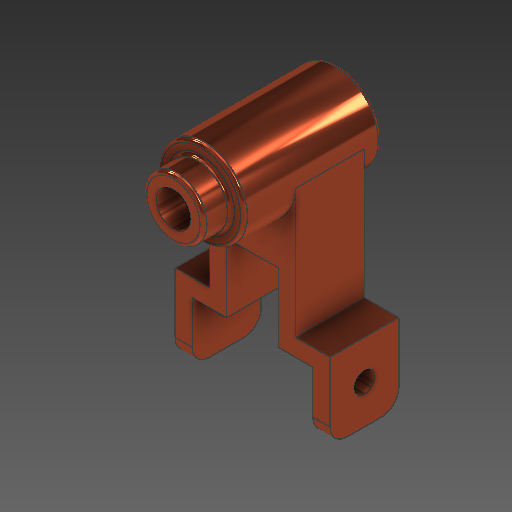
# Autodesk Inventor part: FirstExam
Saved by Autodesk Inventor 2026.1 (Build 301233020, 233B)
## iProperties
Created: 2026-09-07
Part Number: FirstExam
Material: Generic
Document SubType Name: Modeling
Designer: YmCris
Density: 1 g/cm^3
Appearance: Default
Author: YmCris
Autodesk Inventor part; units mm, degrees
ref_plane "YZ Plane" through (0, 0, 0) normal (1, 0, 0) x (0, 1, 0)
ref_plane "XZ Plane" through (0, 0, 0) normal (0, 1, 0) x (-1, 0, 0)
sketch "Sketch1" plane through (0, 0, 0) normal (0, 0, 1) x (1, 0, 0)
  circle A0 centre (0, 0) radius 25
  dimension "d0" = 50
  constraints: 1 centre point, 1 coincident
  measures "d0" diameter of A0
extrude "Extrusion1" add sketch "Sketch1" along normal blind 80
sketch "Sketch2" plane through (0, 0, 80) normal (0, 0, 1) x (1, 0, 0)
  circle A0 centre (0, 0) radius 17.5
  dimension "d3" = 35
  constraints: 1 centre point, 1 coincident
  measures "d3" diameter of A0
extrude "Extrusion2" add sketch "Sketch2" along normal blind 16
sketch "Sketch3" plane through (0, 0, 96) normal (0, 0, 1) x (1, 0, 0)
  circle A0 centre (0, 0) radius 10
  dimension "d6" = 20
  constraints: 1 centre point, 1 coincident
  measures "d6" diameter of A0
extrude "Extrusion3" cut sketch "Sketch3" against normal blind 96
ref_plane "Work Plane1" through (0, 0, 50) normal (0, 0, 1) x (1, 0, 0)
sketch "Sketch4" plane through (0, 0, 50) normal (0, 0, 1) x (1, 0, 0)
  circle A0 centre (0, 0) radius 25 projected
  line L0 (-25, 0) -> (-25, -75)
  line L1 (-25, -75) -> (-45, -75)
  line L2 (-45, -75) -> (-45, -85)
  line L3 (-45, -85) -> (-25, -85)
  line L4 (-25, -85) -> (-15, -85)
  line L5 (-15, -85) -> (-15, -45)
  line L6 (-15, -45) -> (0, -45)
  line L7 (0, -45) -> (0, -25)
  arc A1 (-25, 0) -> (0, -25) centre (0, 0) ccw
  line L8 (0, -75) -> (0, -59.8213) construction
  circle A2 centre (0, 0) radius 25
  line L9 (25, 0) -> (25, -75)
  line L10 (25, -75) -> (45, -75)
  line L11 (45, -85) -> (25, -85)
  line L12 (25, -85) -> (15, -85)
  line L13 (15, -85) -> (15, -45)
  line L14 (15, -45) -> (0, -45)
  line L15 (45, -85) -> (45, -75)
  point P0 (25, 0)
  dimension "d10" = 75
  dimension "d11" = 20
  dimension "d12" = 10
  dimension "d13" = 20
  dimension "d14" = 10
  dimension "d15" = 40
  constraints: 32 end point, 7 symmetric about line, 4 perpendicular, 4 point on circle, 3 vertical, 2 point on line, 1 centre point, 1 concentric, 1 horizontal, 1 horizontal alignment, 1 line through centre, 1 parallel, 1 tangent, 2 other
  measures "d10" distance of L0.start L0.end
  measures "d11" distance of L0.end L1.end
  measures "d12" distance of L1.end L2.end
  measures "d13" distance of L2.end L3.end
  measures "d14" distance of L3.end L4.end
  measures "d15" distance of L4.end L5.end
extrude "Extrusion4" add sketch "Sketch4" against normal blind 40 contours L9 L10 L15 L11 L12 L13 L14 L7 A0 | A0 L7 L6 L5 L4 L3 L2 L1 L0
sketch "Sketch5" plane through (15, -85, 50) normal (0, -1, 0) x (1, 0, 0)
  line L0 (30, 0) -> (30, -40) projected
  line L1 (30, 0) -> (10, 0) projected
  line L2 (30, -40) -> (20, -40)
  line L3 (20, -40) -> (20, 0)
  line L4 (20, 0) -> (30, 0)
  line L5 (30, 0) -> (30, -40)
  point P0 (-15, -50)
  dimension "d18" = 10
  constraints: 8 end point, 2 parallel, 1 horizontal, 1 midpoint, 1 perpendicular
  measures "d18" distance of L3.end L4.end
extrude "Extrusion5" add sketch "Sketch5" along normal blind 35
sketch "Sketch6" plane through (45, -75, 50) normal (1, 0, 0) x (0, 0, -1)
  circle A0 centre (20, -22.5) radius 6
  point P0 (50, 75)
  dimension "d21" = 12
  constraints: 1 centre point
  measures "d21" diameter of A0
extrude "Extrusion6" cut sketch "Sketch6" against normal blind 10
fillet "Fillet1" radius 10 1 edges at (40, -120, 50)
fillet "Fillet2" radius 10 1 edges at (40, -120, 10)
mirror "Mirror1" about plane through (0, 0, 0) normal (1, 0, 0) of "Extrusion5", "Extrusion6", "Fillet2", "Fillet1"
fillet "Fillet3" radius 2 1 edges at (-25, 0, 0)
fillet "Fillet4" radius 2 1 edges at (-25, 0, 80)
fillet "Fillet5" radius 2 1 edges at (-17.5, 0, 96)
fillet "Fillet6" radius 2 1 edges at (-17.5, 0, 80)
body "Solid1"
